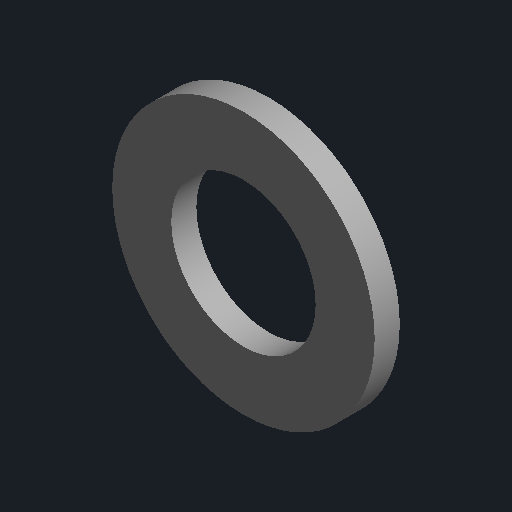
# Autodesk Inventor part: nas620c4l
Saved by Autodesk Inventor 2027.1 (Build 311270010, 270A)
## iProperties
Part Number: nas620c4l
Material: Generic
Document SubType Name: Modeling
Designer: User
Appearance: Steel - Polished
Author: User
Autodesk Inventor part; units mm, degrees
ref_plane "YZ Plane" through (0, 0, 0) normal (1, 0, 0) x (0, 1, 0)
ref_plane "XZ Plane" through (0, 0, 0) normal (0, 1, 0) x (-1, 0, 0)
ref_plane "XY Plane" through (0, 0, 0) normal (0, 0, 1) x (1, 0, 0)
sketch "Sketch1" plane through (0, 0, 0) normal (0, 0, 1) x (1, 0, 0)
  circle A0 centre (0, 0) radius 2.6543
  circle A1 centre (0, 0) radius 1.4605
  dimension "d0" = 0.508
  constraints: 2 centre point
extrude "Extrusion1" add sketch "Sketch1" along normal blind 0.508
body "Solid1"
